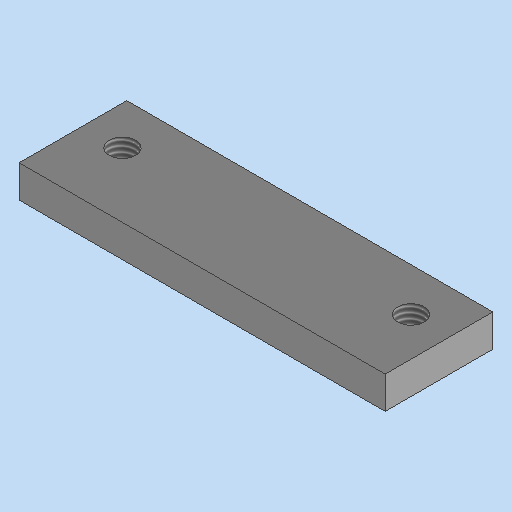
# Autodesk Inventor part: MM0948AN140_G01_123
Saved by Autodesk Inventor 2023.3 (Build 273359000, 359)
## iProperties
Created: 2023-09-05
Part Number: MM0948AN140_G01_123
Material: 1.2842 90MnCrV8
Description: =<RBPARTNOTITLE2>
Document SubType Name: Modeling
Designer: RIC7AN
Mass: 7.78332 g
Surface Area: 9.71355 cm^2
Volume: 0.991506 cm^3
Density: 7.85 g/cm^3
Appearance: Stahl - normal AnP
RBPARTMADEOF: 3 x 10 x 34 (FM)
RBDRAWINGMISSINGSPEC: --
AnP_Kategorie: 1
RBPARTNOTITLE2: Anfertigungsteil
RBSURFACE: --
RBPARTNOTITLE1: manufactured part
RBSURFACE2: --
AnP_Material: =<Material>
RBMATERIAL: =<Material>
RBMATNO: =<Part Number>
RBPARTNO: SIEHE MNR
MaxAbmaße: 3 x 10 x 34 (FM)
Author: RIC7AN
Keywords: =<RBPARTMADEOF>
Comments: =<RBSURFACE2>
Revision Number: 01
Autodesk Inventor part; units mm, degrees
ref_plane "YZ Plane" through (0, 0, 0) normal (1, 0, 0) x (0, 1, 0)
ref_plane "XZ Plane" through (0, 0, 0) normal (0, 1, 0) x (-1, 0, 0)
ref_plane "XY Plane" through (0, 0, 0) normal (0, 0, 1) x (1, 0, 0)
sketch "Skizze1" plane through (0, 0, 0) normal (0, 0, 1) x (1, 0, 0)
  line L0 (-17, 5) -> (17, 5)
  line L1 (17, 5) -> (17, -5)
  line L2 (17, -5) -> (-17, -5)
  line L3 (-17, -5) -> (-17, 5)
  line L4 (0, 7) -> (0, -7) projected
  line L5 (-23.8, 0) -> (23.8, 0) projected
  point P0 (0, 0)
  dimension "d0" = 34
  dimension "d1" = 10
  constraints: 8 end point, 2 parallel, 1 horizontal, 1 perpendicular, 2 other
  measures "d0" distance of L0.start L0.end
  measures "d1" distance of L0.end L1.end
extrude "Extrusion1" add sketch "Skizze1" along normal blind 3
sketch "Skizze2" plane through (0, 0, 3) normal (0, 0, 1) x (1, 0, 0)
  line L0 (0, 7) -> (0, -7) projected
  line L1 (-23.8, 0) -> (23.8, 0) projected
  point P0 (0, 0)
  point P1 (-13.4, 1)
  point P2 (13.4, 1)
  dimension "d4" = 26.8
  dimension "d12" = 1
  constraints: 1 symmetric about line
  measures "d4" distance of point (13.4, 1) point (-13.4, 1)
  measures "d12" distance from line of L1 point (-13.4, 1)
hole "Bohrung1" at (-13.4, 1, 3) at (13.4, 1, 3) direction (0, 0, -1) diameter 2.459 end through all thread size "M3x0.5" designation "M3" class "6H" standard "ISO Metric profile"
